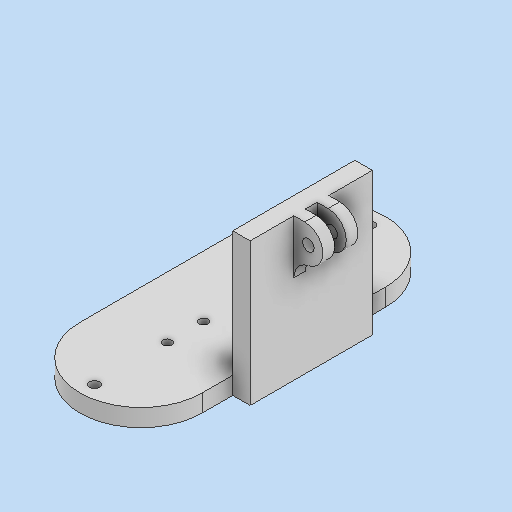
# Autodesk Inventor part: realsense_d405_mounting_top
Saved by Autodesk Inventor 2026.2 (Build 302298000, 298)
## iProperties
Created: 2025-11-05
Part Number: realsense_d405_mounting_top
Material: Generic
Document SubType Name: Modeling
Designer: mobimobi
Density: 1 g/cm^3
Appearance: Default
Author: mobimobi
Autodesk Inventor part; units mm, degrees
ref_plane "YZ Plane" through (0, 0, 0) normal (1, 0, 0) x (0, 1, 0)
ref_plane "XZ Plane" through (0, 0, 0) normal (0, 1, 0) x (-1, 0, 0)
ref_plane "XY Plane" through (0, 0, 0) normal (0, 0, 1) x (1, 0, 0)
sketch "Sketch1" plane through (0, 0, 0) normal (0, 1, 0) x (-1, 0, 0)
  line L0 (5, -2) -> (-5, -2)
  line L1 (-5, -2) -> (-5, 2)
  line L2 (-5, 2) -> (5, 2)
  line L3 (5, 2) -> (5, -2)
  line L4 (5, -2) -> (-5, 2) construction
  line L5 (-5, -2) -> (5, 2) construction
  line L6 (5, -2) -> (-5, -2)
  line L7 (-5, -2) -> (-5, -6)
  line L8 (-5, -6) -> (5, -6)
  line L9 (5, -6) -> (5, -2)
  line L10 (5, 2) -> (-5, 2)
  line L11 (-5, 2) -> (-5, 6)
  line L12 (-5, 6) -> (5, 6)
  line L13 (5, 6) -> (5, 2)
  line L14 (5, -6) -> (11, -6)
  line L15 (11, -6) -> (11, 6)
  line L16 (11, 6) -> (5, 6)
  line L17 (5, 6) -> (5, -6)
  line L18 (11, -10.75) -> (5, -10.75)
  line L19 (5, -10.75) -> (5, 10.75)
  line L20 (5, 10.75) -> (11, 10.75)
  line L21 (11, 10.75) -> (11, -10.75)
  line L22 (11, -10.75) -> (5, 10.75) construction
  line L23 (5, -10.75) -> (11, 10.75) construction
  point P0 (0, 0)
  point P1 (8, 0)
  dimension "d0" = 10
  dimension "d1" = 4
  dimension "d2" = 4
  dimension "d3" = 10
  dimension "d4" = 4
  dimension "d5" = 6
  dimension "d6" = 6
  dimension "d7" = 21.5
  constraints: 48 end point, 10 parallel, 5 horizontal, 5 perpendicular, 4 midpoint
  measures "d0" distance of L1.end L2.end
  measures "d1" distance of L0.end L1.end
  measures "d2" distance of L7.end L6.end
  measures "d3" distance of L11.end L12.end
  measures "d4" distance of L10.end L11.end
  measures "d5" distance of L16.end L15.end
  measures "d6" distance of L19.end L20.end
  measures "d7" distance of L18.end L19.end
extrude "Extrusion1" add sketch "Sketch1" along normal blind 12.5 contours L9 L8 L7 L0 | L3 L13 L16 L15 L14 L9 | L2 L11 L12 L13 | L14 L21 L18 L19 | L19 L20 L21 L16
sketch "Sketch2" plane through (-5, 0, 6) normal (0, 0, 1) x (1, 0, 0)
  line L0 (0, 12.5) -> (10, 12.5) projected
  line L1 (0, 0) -> (10, 0) projected
  line L2 (10, 12.5) -> (0, 0)
  line L3 (0, 0) -> (10, 0)
  line L4 (10, 0) -> (0, 12.5)
  line L5 (0, 12.5) -> (10, 12.5)
  circle A0 centre (5, 6.25) radius 2
  point P0 (5, 0)
  dimension "d10" = 4
  constraints: 8 end point, 2 equal length, 1 centre point, 1 midpoint
  measures "d10" diameter of A0
extrude "Extrusion2" cut sketch "Sketch2" against normal blind 12.5 contours A0 L2 L4 | L4 L2 A0 | A0 L4 L2 | L4 A0 L2
fillet "Fillet1" radius 6.25 4 edges at (5, 0, 4) (5, 12.5, 4) (5, 12.5, -4) (5, 0, -4)
sketch "Sketch3" plane through (-11, 0, -10.75) normal (-1, 0, 0) x (0, 0, 1)
  line L0 (0, 0) -> (21.5, 0) projected
  line L1 (4.75, 12.5) -> (0, 12.5) projected
  line L2 (21.5, 0) -> (0, 12.5)
  line L3 (0, 12.5) -> (0, 0)
  line L4 (0, 12.5) -> (21.5, 12.5) projected
  line L5 (0, 0) -> (21.5, 12.5)
  line L6 (21.5, 12.5) -> (21.5, 0)
  line L7 (-10.25, 0) -> (31.75, 0)
  line L8 (31.75, 0) -> (31.75, 12.5)
  line L9 (31.75, 12.5) -> (-10.25, 12.5)
  line L10 (-10.25, 12.5) -> (-10.25, 0)
  line L11 (-10.25, 0) -> (31.75, 12.5) construction
  line L12 (31.75, 0) -> (-10.25, 12.5) construction
  point P0 (10.75, 0)
  point P1 (10.75, 6.25)
  dimension "d14" = 42
  dimension "d15" = 12.5
  constraints: 20 end point, 3 midpoint, 3 perpendicular, 2 parallel, 1 horizontal
  measures "d14" distance of L9.end L8.end
  measures "d15" distance of L8.end L7.end
extrude "Extrusion3" add sketch "Sketch3" against normal blind 6 contours L7 L10 L9 L3 | L6 L9 L8 L7
sketch "Sketch4" plane through (0, 0, 0) normal (0, -1, 0) x (1, 0, 0)
  line L0 (-11, -21) -> (-11, 21) projected
  line L1 (-5, 21) -> (-5, 6) projected
  line L2 (-11, -21) -> (-5, -21)
  line L3 (-5, -21) -> (-5, 21)
  line L4 (-5, 21) -> (-11, 21)
  line L5 (-11, 21) -> (-11, -21)
  point P0 (0, 0)
  constraints: 8 end point, 2 parallel, 1 horizontal, 1 perpendicular
extrude "Extrusion4" add sketch "Sketch4" along normal blind 16.5
fillet "Fillet2" radius 6.25 2 edges at (-5, 0, 4) (-5, 0, -4)
sketch "Sketch8" plane through (-5, 12.5, -21) normal (0, 0, -1) x (-1, 0, 0)
  line L0 (6, -23) -> (6, -29) projected
  line L1 (6, -23) -> (0, -23)
  line L2 (0, -23) -> (0, -49)
  line L3 (0, -49) -> (6, -49)
  line L4 (6, -49) -> (6, -23)
  line L5 (6, -29) -> (48, -29) projected
  line L6 (6, -49) -> (48, -49)
  line L7 (48, -49) -> (48, -29)
  line L8 (48, -29) -> (6, -29)
  line L9 (6, -29) -> (6, -49)
  point P0 (-5, -12.5)
  dimension "d41" = 6
  dimension "d42" = 26
  constraints: 16 end point, 4 parallel, 2 horizontal, 2 perpendicular
  measures "d41" distance of L3.end L2.end
  measures "d42" distance of L2.end L1.end
extrude "Extrusion8" add sketch "Sketch8" against normal blind 42 contours L0 L4 L3 L2 L1
sketch "Sketch9" plane through (-11, -36.5, -21) normal (0, -1, 0) x (1, 0, 0)
  line L0 (-42, -31.5) -> (0, -31.5) projected
  line L1 (0, 73.5) -> (-42, 73.5) projected
  line L2 (-42, -31.5) -> (0, -31.5)
  line L3 (0, -31.5) -> (0, 73.5)
  line L4 (0, 73.5) -> (-42, 73.5)
  line L5 (-42, 73.5) -> (-42, -31.5)
  circle A0 centre (-21, -26.5) radius 1.5 projected
  circle A1 centre (-21, -26.5) radius 1.5
  circle A2 centre (-21, -1.5) radius 1.5 projected
  circle A3 centre (-21, -1.5) radius 1.5
  circle A4 centre (-21, 11) radius 1.5 projected
  circle A5 centre (-21, 11) radius 1.5
  circle A6 centre (-21, 31) radius 1.5 projected
  circle A7 centre (-21, 31) radius 1.5
  circle A8 centre (-21, 43.5) radius 1.5 projected
  circle A9 centre (-21, 43.5) radius 1.5
  circle A10 centre (-21, 68.5) radius 1.6949 projected
  circle A11 centre (-21, 68.5) radius 1.6949
  point P0 (11, 21)
  point P1 (0, -31.5)
  constraints: 8 end point, 6 centre point, 6 coincident, 2 parallel, 1 horizontal, 1 perpendicular
extrude "Extrusion9" add sketch "Sketch9" against normal blind 6
fillet "Fillet3" radius 21 4 edges at (-53, -33.5, -52.5) (-11, -33.5, -52.5) (-53, -33.5, 52.5) (-11, -33.5, 52.5)
body "Solid1"
